F1GameStation_blockout (Autodesk Fusion 360 design; units mm, degrees)
Autodesk Fusion 360 part; units mm, degrees
sketch "Layout (front view)" plane through (0, 0, 0) normal (0, 0, 1) x (1, 0, 0)
  line L0 (-93, -40) -> (93, -40)
  line L1 (93, -40) -> (93, 40)
  line L2 (93, 40) -> (-93, 40)
  line L3 (-93, 40) -> (-93, -40)
  line L4 (-53, -33) -> (53, -33)
  line L5 (53, -33) -> (53, 34)
  line L6 (53, 34) -> (-53, 34)
  line L7 (-53, 34) -> (-53, -33)
  line L8 (-49.5, -30) -> (49.5, -30)
  line L9 (49.5, -30) -> (49.5, 26.5)
  line L10 (49.5, 26.5) -> (-49.5, 26.5)
  line L11 (-49.5, 26.5) -> (-49.5, -30)
  circle A0 centre (-73, 21) radius 3.5
  circle A1 centre (-73, 3) radius 3.5
  circle A2 centre (-82, 12) radius 3.5
  circle A3 centre (-64, 12) radius 3.5
  circle A4 centre (73, 21) radius 3.5
  circle A5 centre (73, 3) radius 3.5
  circle A6 centre (64, 12) radius 3.5
  circle A7 centre (82, 12) radius 3.5
  circle A8 centre (65.5, -18) radius 2.5
  circle A9 centre (80.5, -18) radius 2.5
  circle A10 centre (73, -29) radius 2.5
  line L12 (-78, -25.6) -> (-68, -25.6)
  line L13 (-68, -25.6) -> (-68, -24.4)
  line L14 (-68, -24.4) -> (-78, -24.4)
  line L15 (-78, -24.4) -> (-78, -25.6)
  line L16 (-78, -22.6) -> (-68, -22.6)
  line L17 (-68, -22.6) -> (-68, -21.4)
  line L18 (-68, -21.4) -> (-78, -21.4)
  line L19 (-78, -21.4) -> (-78, -22.6)
  line L20 (-78, -19.6) -> (-68, -19.6)
  line L21 (-68, -19.6) -> (-68, -18.4)
  line L22 (-68, -18.4) -> (-78, -18.4)
  line L23 (-78, -18.4) -> (-78, -19.6)
  dimension "d46" = 186
  dimension "d47" = 80
  dimension "d48" = 93
  dimension "d49" = 40
  dimension "d50" = 106
  dimension "d51" = 67
  dimension "d52" = 53
  dimension "d53" = 33
  dimension "d54" = 99
  dimension "d56" = 49.5
  dimension "d57" = 30
  dimension "d58" = 7
  dimension "d59" = 73
  dimension "d60" = 21
  dimension "d61" = 7
  dimension "d62" = 73
  dimension "d63" = 3
  dimension "d64" = 7
  dimension "d65" = 82
  dimension "d66" = 12
  dimension "d67" = 7
  dimension "d68" = 64
  dimension "d69" = 12
  dimension "d70" = 7
  dimension "d71" = 73
  dimension "d72" = 21
  dimension "d73" = 7
  dimension "d74" = 73
  dimension "d75" = 3
  dimension "d76" = 7
  dimension "d77" = 64
  dimension "d78" = 12
  dimension "d79" = 7
  dimension "d80" = 82
  dimension "d81" = 12
  dimension "d82" = 5
  dimension "d83" = 65.5
  dimension "d84" = 18
  dimension "d85" = 5
  dimension "d86" = 80.5
  dimension "d87" = 18
  dimension "d88" = 5
  dimension "d89" = 73
  dimension "d90" = 29
  dimension "d91" = 10
  dimension "d92" = 1.2
  dimension "d93" = 78
  dimension "d94" = 25.6
  dimension "d95" = 10
  dimension "d96" = 1.2
  dimension "d97" = 78
  dimension "d98" = 22.6
  dimension "d99" = 10
  dimension "d100" = 1.2
  dimension "d101" = 78
  dimension "d102" = 19.6
  constraint horizontal L0
  constraint horizontal L2
  constraint vertical L1
  constraint vertical L3
  constraint horizontal L4
  constraint horizontal L6
  constraint vertical L5
  constraint vertical L7
  constraint horizontal L8
  constraint horizontal L10
  constraint vertical L9
  constraint vertical L11
  constraint horizontal L12
  constraint horizontal L14
  constraint vertical L13
  constraint vertical L15
  constraint horizontal L16
  constraint horizontal L18
  constraint vertical L17
  constraint vertical L19
  constraint horizontal L20
  constraint horizontal L22
  constraint vertical L21
  constraint vertical L23
  measures "d46" horizontal distance of L0.start L0.end
  measures "d47" vertical distance of L0.end L1.end
  measures "d48" horizontal distance of origin L0.start
  measures "d49" vertical distance of origin L0.start
  measures "d50" horizontal distance of L4.start L4.end
  measures "d51" vertical distance of L4.end L5.end
  measures "d52" horizontal distance of origin L4.start
  measures "d53" vertical distance of origin L4.start
  measures "d54" horizontal distance of L8.start L8.end
  measures "d56" horizontal distance of origin L8.start
  measures "d57" vertical distance of origin L8.start
  measures "d58" diameter of A0
  measures "d59" horizontal distance of origin A0.centre
  measures "d60" vertical distance of origin A0.centre
  measures "d61" diameter of A1
  measures "d62" horizontal distance of origin A1.centre
  measures "d63" vertical distance of origin A1.centre
  measures "d64" diameter of A2
  measures "d65" horizontal distance of origin A2.centre
  measures "d66" vertical distance of origin A2.centre
  measures "d67" diameter of A3
  measures "d68" horizontal distance of origin A3.centre
  measures "d69" vertical distance of origin A3.centre
  measures "d70" diameter of A4
  measures "d71" horizontal distance of origin A4.centre
  measures "d72" vertical distance of origin A4.centre
  measures "d73" diameter of A5
  measures "d74" horizontal distance of origin A5.centre
  measures "d75" vertical distance of origin A5.centre
  measures "d76" diameter of A6
  measures "d77" horizontal distance of origin A6.centre
  measures "d78" vertical distance of origin A6.centre
  measures "d79" diameter of A7
  measures "d80" horizontal distance of origin A7.centre
  measures "d81" vertical distance of origin A7.centre
  measures "d82" diameter of A8
  measures "d83" horizontal distance of origin A8.centre
  measures "d84" vertical distance of origin A8.centre
  measures "d85" diameter of A9
  measures "d86" horizontal distance of origin A9.centre
  measures "d87" vertical distance of origin A9.centre
  measures "d88" diameter of A10
  measures "d89" horizontal distance of origin A10.centre
  measures "d90" vertical distance of origin A10.centre
  measures "d91" horizontal distance of L12.start L12.end
  measures "d92" vertical distance of L12.end L13.end
  measures "d93" horizontal distance of origin L12.start
  measures "d94" vertical distance of origin L12.start
  measures "d95" horizontal distance of L16.start L16.end
  measures "d96" vertical distance of L16.end L17.end
  measures "d97" horizontal distance of origin L16.start
  measures "d98" vertical distance of origin L16.start
  measures "d99" horizontal distance of L20.start L20.end
  measures "d100" vertical distance of L20.end L21.end
  measures "d101" horizontal distance of origin L20.start
  measures "d102" vertical distance of origin L20.start
ref_plane "WorkPlane1" through (0, 0, -1.6) normal (0, 0, 1) x (1, 0, 0) in component "Board envelope"
sketch "PCB" plane through (0, 0, -1.6) normal (0, 0, 1) x (1, 0, 0) in component "Board envelope"
  line L0 (-88, -35) -> (88, -35)
  line L1 (88, -35) -> (88, 35)
  line L2 (88, 35) -> (-88, 35)
  line L3 (-88, 35) -> (-88, -35)
  dimension "d105" = 176
  dimension "d106" = 70
  dimension "d107" = 88
  dimension "d108" = 35
  constraint horizontal L0
  constraint horizontal L2
  constraint vertical L1
  constraint vertical L3
  measures "d105" horizontal distance of L0.start L0.end
  measures "d106" vertical distance of L0.end L1.end
  measures "d107" horizontal distance of origin L0.start
  measures "d108" vertical distance of origin L0.start
extrude "Extrude1" add sketch "PCB" along normal blind 1.6 makes body 1 in component "Board envelope"
ref_plane "WorkPlane1" through (0, 0, 1) normal (0, 0, 1) x (1, 0, 0) in component "LCD FPC043CS4001"
sketch "LCD module" plane through (0, 0, 1) normal (0, 0, 1) x (1, 0, 0) in component "LCD FPC043CS4001"
  line L0 (-53, -33) -> (53, -33)
  line L1 (53, -33) -> (53, 34)
  line L2 (53, 34) -> (-53, 34)
  line L3 (-53, 34) -> (-53, -33)
  dimension "d113" = 106
  dimension "d114" = 67
  dimension "d115" = 53
  dimension "d116" = 33
  constraint horizontal L0
  constraint horizontal L2
  constraint vertical L1
  constraint vertical L3
  measures "d113" horizontal distance of L0.start L0.end
  measures "d114" vertical distance of L0.end L1.end
  measures "d115" horizontal distance of origin L0.start
  measures "d116" vertical distance of origin L0.start
extrude "Extrude1'" add sketch "LCD module" along normal blind 3 separate body makes body 2 in component "LCD FPC043CS4001"
ref_plane "WorkPlane2" through (0, 0, 4) normal (0, 0, 1) x (1, 0, 0) in component "LCD FPC043CS4001"
sketch "LCD visible area" plane through (0, 0, 4) normal (0, 0, 1) x (1, 0, 0) in component "LCD FPC043CS4001"
  line L0 (-49.5, -30) -> (49.5, -30)
  line L1 (49.5, -30) -> (49.5, 26.5)
  line L2 (49.5, 26.5) -> (-49.5, 26.5)
  line L3 (-49.5, 26.5) -> (-49.5, -30)
  dimension "d121" = 99
  dimension "d123" = 49.5
  dimension "d124" = 30
  constraint horizontal L0
  constraint horizontal L2
  constraint vertical L1
  constraint vertical L3
  measures "d121" horizontal distance of L0.start L0.end
  measures "d123" horizontal distance of origin L0.start
  measures "d124" vertical distance of origin L0.start
extrude "Extrude2" add sketch "LCD visible area" along normal blind 0.1 separate body makes body 3 in component "LCD FPC043CS4001"
ref_plane "WorkPlane3" through (0, 0, 0.2) normal (0, 0, 1) x (1, 0, 0) in component "LCD FPC043CS4001"
sketch "FPC wrap" plane through (0, 0, 0.2) normal (0, 0, 1) x (1, 0, 0) in component "LCD FPC043CS4001"
  line L0 (-15, 34) -> (31, 34)
  line L1 (31, 34) -> (31, 34.6)
  line L2 (31, 34.6) -> (-15, 34.6)
  line L3 (-15, 34.6) -> (-15, 34)
  dimension "d129" = 46
  dimension "d130" = 0.6
  dimension "d132" = 34
  dimension "d272" = 15
  constraint horizontal L0
  constraint horizontal L2
  constraint vertical L1
  constraint vertical L3
  measures "d129" horizontal distance of L0.start L0.end
  measures "d130" vertical distance of L0.end L1.end
  measures "d132" vertical distance of origin L0.start
  measures "d272" horizontal distance of origin L0.start
extrude "Extrude3" add sketch "FPC wrap" along normal blind 3.8 separate body makes body 4 in component "LCD FPC043CS4001"
ref_plane "WorkPlane4" through (0, 0, 0.2) normal (0, 0, 1) x (1, 0, 0) in component "LCD FPC043CS4001"
sketch "FPC tail" plane through (0, 0, 0.2) normal (0, 0, 1) x (1, 0, 0) in component "LCD FPC043CS4001"
  line L0 (-15, 2) -> (31, 2)
  line L1 (31, 2) -> (31, 34)
  line L2 (31, 34) -> (-15, 34)
  line L3 (-15, 34) -> (-15, 2)
  dimension "d137" = 46
  dimension "d138" = 32
  dimension "d140" = 2
  dimension "d273" = 15
  constraint horizontal L0
  constraint horizontal L2
  constraint vertical L1
  constraint vertical L3
  measures "d137" horizontal distance of L0.start L0.end
  measures "d138" vertical distance of L0.end L1.end
  measures "d140" vertical distance of origin L0.start
  measures "d273" horizontal distance of origin L0.start
extrude "Extrude4" add sketch "FPC tail" along normal blind 0.3 separate body makes body 5 in component "LCD FPC043CS4001"
ref_plane "WorkPlane1" through (0, 0, -10.1) normal (0, 0, 1) x (1, 0, 0) in component "Battery 606090"
sketch "Battery" plane through (0, 0, -10.1) normal (0, 0, 1) x (1, 0, 0) in component "Battery 606090"
  line L0 (-45, -27.5) -> (45, -27.5)
  line L1 (45, -27.5) -> (45, 32.5)
  line L2 (45, 32.5) -> (-45, 32.5)
  line L3 (-45, 32.5) -> (-45, -27.5)
  dimension "d145" = 90
  dimension "d146" = 60
  dimension "d147" = 45
  dimension "d349" = 27.5
  constraint horizontal L0
  constraint horizontal L2
  constraint vertical L1
  constraint vertical L3
  measures "d145" horizontal distance of L0.start L0.end
  measures "d146" vertical distance of L0.end L1.end
  measures "d147" horizontal distance of origin L0.start
  measures "d349" vertical distance of origin L0.start
extrude "Extrude1''" add sketch "Battery" along normal blind 6 separate body makes body 6 in component "Battery 606090"
ref_plane "WorkPlane1" through (0, 0, 0) normal (0, 0, 1) x (1, 0, 0) in component "Buttons"
sketch "Face buttons 1" plane through (0, 0, 0) normal (0, 0, 1) x (1, 0, 0) in component "Buttons"
  circle A0 centre (-73, 21) radius 3.5
  dimension "d153" = 7
  dimension "d154" = 73
  dimension "d155" = 21
  measures "d153" diameter of A0
  measures "d154" horizontal distance of origin A0.centre
  measures "d155" vertical distance of origin A0.centre
extrude "Extrude1'''" add sketch "Face buttons 1" along normal blind 4.5 separate body makes body 7 in component "Buttons"
sketch "Face buttons 2" plane through (0, 0, 0) normal (0, 0, 1) x (1, 0, 0) in component "Buttons"
  circle A0 centre (-73, 3) radius 3.5
  dimension "d158" = 7
  dimension "d159" = 73
  dimension "d160" = 3
  measures "d158" diameter of A0
  measures "d159" horizontal distance of origin A0.centre
  measures "d160" vertical distance of origin A0.centre
extrude "Extrude2'" add sketch "Face buttons 2" along normal blind 4.5 separate body makes body 8 in component "Buttons"
sketch "Face buttons 3" plane through (0, 0, 0) normal (0, 0, 1) x (1, 0, 0) in component "Buttons"
  circle A0 centre (-82, 12) radius 3.5
  dimension "d163" = 7
  dimension "d164" = 82
  dimension "d165" = 12
  measures "d163" diameter of A0
  measures "d164" horizontal distance of origin A0.centre
  measures "d165" vertical distance of origin A0.centre
extrude "Extrude3'" add sketch "Face buttons 3" along normal blind 4.5 separate body makes body 9 in component "Buttons"
sketch "Face buttons 4" plane through (0, 0, 0) normal (0, 0, 1) x (1, 0, 0) in component "Buttons"
  circle A0 centre (-64, 12) radius 3.5
  dimension "d168" = 7
  dimension "d169" = 64
  dimension "d170" = 12
  measures "d168" diameter of A0
  measures "d169" horizontal distance of origin A0.centre
  measures "d170" vertical distance of origin A0.centre
extrude "Extrude4'" add sketch "Face buttons 4" along normal blind 4.5 separate body makes body 10 in component "Buttons"
sketch "Face buttons 5" plane through (0, 0, 0) normal (0, 0, 1) x (1, 0, 0) in component "Buttons"
  circle A0 centre (73, 21) radius 3.5
  dimension "d173" = 7
  dimension "d174" = 73
  dimension "d175" = 21
  measures "d173" diameter of A0
  measures "d174" horizontal distance of origin A0.centre
  measures "d175" vertical distance of origin A0.centre
extrude "Extrude5" add sketch "Face buttons 5" along normal blind 4.5 separate body makes body 11 in component "Buttons"
sketch "Face buttons 6" plane through (0, 0, 0) normal (0, 0, 1) x (1, 0, 0) in component "Buttons"
  circle A0 centre (73, 3) radius 3.5
  dimension "d178" = 7
  dimension "d179" = 73
  dimension "d180" = 3
  measures "d178" diameter of A0
  measures "d179" horizontal distance of origin A0.centre
  measures "d180" vertical distance of origin A0.centre
extrude "Extrude6" add sketch "Face buttons 6" along normal blind 4.5 separate body makes body 12 in component "Buttons"
sketch "Face buttons 7" plane through (0, 0, 0) normal (0, 0, 1) x (1, 0, 0) in component "Buttons"
  circle A0 centre (64, 12) radius 3.5
  dimension "d183" = 7
  dimension "d184" = 64
  dimension "d185" = 12
  measures "d183" diameter of A0
  measures "d184" horizontal distance of origin A0.centre
  measures "d185" vertical distance of origin A0.centre
extrude "Extrude7" add sketch "Face buttons 7" along normal blind 4.5 separate body makes body 13 in component "Buttons"
sketch "Face buttons 8" plane through (0, 0, 0) normal (0, 0, 1) x (1, 0, 0) in component "Buttons"
  circle A0 centre (82, 12) radius 3.5
  dimension "d188" = 7
  dimension "d189" = 82
  dimension "d190" = 12
  measures "d188" diameter of A0
  measures "d189" horizontal distance of origin A0.centre
  measures "d190" vertical distance of origin A0.centre
extrude "Extrude8" add sketch "Face buttons 8" along normal blind 4.5 separate body makes body 14 in component "Buttons"
ref_plane "WorkPlane2" through (0, 0, 0) normal (0, 0, 1) x (1, 0, 0) in component "Buttons"
sketch "Start Select Menu 1" plane through (0, 0, 0) normal (0, 0, 1) x (1, 0, 0) in component "Buttons"
  circle A0 centre (65.5, -18) radius 2.5
  dimension "d195" = 5
  dimension "d196" = 65.5
  dimension "d197" = 18
  measures "d195" diameter of A0
  measures "d196" horizontal distance of origin A0.centre
  measures "d197" vertical distance of origin A0.centre
extrude "Extrude9" add sketch "Start Select Menu 1" along normal blind 4.5 separate body makes body 15 in component "Buttons"
sketch "Start Select Menu 2" plane through (0, 0, 0) normal (0, 0, 1) x (1, 0, 0) in component "Buttons"
  circle A0 centre (80.5, -18) radius 2.5
  dimension "d200" = 5
  dimension "d201" = 80.5
  dimension "d202" = 18
  measures "d200" diameter of A0
  measures "d201" horizontal distance of origin A0.centre
  measures "d202" vertical distance of origin A0.centre
extrude "Extrude10" add sketch "Start Select Menu 2" along normal blind 4.5 separate body makes body 16 in component "Buttons"
sketch "Start Select Menu 3" plane through (0, 0, 0) normal (0, 0, 1) x (1, 0, 0) in component "Buttons"
  circle A0 centre (73, -29) radius 2.5
  dimension "d205" = 5
  dimension "d206" = 73
  dimension "d207" = 29
  measures "d205" diameter of A0
  measures "d206" horizontal distance of origin A0.centre
  measures "d207" vertical distance of origin A0.centre
extrude "Extrude11" add sketch "Start Select Menu 3" along normal blind 4.5 separate body makes body 17 in component "Buttons"
ref_plane "WorkPlane3" through (0, 0, 0) normal (0, 0, 1) x (1, 0, 0) in component "Buttons"
ref_plane "WorkPlane4" through (0, 0, 0) normal (0, 0, 1) x (1, 0, 0) in component "Buttons"
sketch "L R switches 1" plane through (0, 0, 0) normal (0, 0, 1) x (1, 0, 0) in component "Buttons"
  line L0 (-82.25, 31.6) -> (-77.75, 31.6)
  line L1 (-77.75, 31.6) -> (-77.75, 35)
  line L2 (-77.75, 35) -> (-82.25, 35)
  line L3 (-82.25, 35) -> (-82.25, 31.6)
  dimension "d220" = 4.5
  dimension "d221" = 3.4
  dimension "d222" = 82.25
  dimension "d223" = 31.6
  constraint horizontal L0
  constraint horizontal L2
  constraint vertical L1
  constraint vertical L3
  measures "d220" horizontal distance of L0.start L0.end
  measures "d221" vertical distance of L0.end L1.end
  measures "d222" horizontal distance of origin L0.start
  measures "d223" vertical distance of origin L0.start
extrude "Extrude13" add sketch "L R switches 1" along normal blind 3.3 separate body makes body 18 in component "Buttons"
sketch "L R switches 2" plane through (0, 0, 0) normal (0, 0, 1) x (1, 0, 0) in component "Buttons"
  line L0 (77.75, 31.6) -> (82.25, 31.6)
  line L1 (82.25, 31.6) -> (82.25, 35)
  line L2 (82.25, 35) -> (77.75, 35)
  line L3 (77.75, 35) -> (77.75, 31.6)
  dimension "d226" = 4.5
  dimension "d227" = 3.4
  dimension "d228" = 77.75
  dimension "d229" = 31.6
  constraint horizontal L0
  constraint horizontal L2
  constraint vertical L1
  constraint vertical L3
  measures "d226" horizontal distance of L0.start L0.end
  measures "d227" vertical distance of L0.end L1.end
  measures "d228" horizontal distance of origin L0.start
  measures "d229" vertical distance of origin L0.start
extrude "Extrude14" add sketch "L R switches 2" along normal blind 3.3 separate body makes body 19 in component "Buttons"
ref_plane "WorkPlane1" through (0, 0, -4.86) normal (0, 0, 1) x (1, 0, 0) in component "Connectors"
sketch "USB-C" plane through (0, 0, -4.86) normal (0, 0, 1) x (1, 0, 0) in component "Connectors"
  line L0 (-4.47, -36) -> (4.47, -36)
  line L1 (4.47, -36) -> (4.47, -28.65)
  line L2 (4.47, -28.65) -> (-4.47, -28.65)
  line L3 (-4.47, -28.65) -> (-4.47, -36)
  dimension "d234" = 8.94
  dimension "d235" = 7.35
  dimension "d236" = 4.47
  dimension "d237" = 36
  constraint horizontal L0
  constraint horizontal L2
  constraint vertical L1
  constraint vertical L3
  measures "d234" horizontal distance of L0.start L0.end
  measures "d235" vertical distance of L0.end L1.end
  measures "d236" horizontal distance of origin L0.start
  measures "d237" vertical distance of origin L0.start
extrude "Extrude1''''" add sketch "USB-C" along normal blind 3.26 separate body makes body 20 in component "Connectors"
ref_plane "WorkPlane2" through (0, 0, -3.45) normal (0, 0, 1) x (1, 0, 0) in component "Connectors"
sketch "TF slot" plane through (0, 0, -3.45) normal (0, 0, 1) x (1, 0, 0) in component "Connectors"
  line L0 (45, -36) -> (59, -36)
  line L1 (59, -36) -> (59, -21)
  line L2 (59, -21) -> (45, -21)
  line L3 (45, -21) -> (45, -36)
  dimension "d242" = 14
  dimension "d243" = 15
  dimension "d244" = 45
  dimension "d245" = 36
  constraint horizontal L0
  constraint horizontal L2
  constraint vertical L1
  constraint vertical L3
  measures "d242" horizontal distance of L0.start L0.end
  measures "d243" vertical distance of L0.end L1.end
  measures "d244" horizontal distance of origin L0.start
  measures "d245" vertical distance of origin L0.start
extrude "Extrude2''" add sketch "TF slot" along normal blind 1.85 separate body makes body 21 in component "Connectors"
ref_plane "WorkPlane3" through (0, 0, -5.9) normal (0, 0, 1) x (1, 0, 0) in component "Connectors"
sketch "Battery connector" plane through (0, 0, -5.9) normal (0, 0, 1) x (1, 0, 0) in component "Connectors"
  line L0 (50, -1.5) -> (56, -1.5)
  line L1 (56, -1.5) -> (56, 6.5)
  line L2 (56, 6.5) -> (50, 6.5)
  line L3 (50, 6.5) -> (50, -1.5)
  dimension "d250" = 6
  dimension "d251" = 8
  dimension "d252" = 50
  dimension "d350" = 1.5
  constraint horizontal L0
  constraint horizontal L2
  constraint vertical L1
  constraint vertical L3
  measures "d250" horizontal distance of L0.start L0.end
  measures "d251" vertical distance of L0.end L1.end
  measures "d252" horizontal distance of origin L0.start
  measures "d350" vertical distance of origin L0.start
extrude "Extrude3''" add sketch "Battery connector" along normal blind 4.3 separate body makes body 22 in component "Connectors"
ref_plane "WorkPlane1" through (0, 0, 0) normal (0, 0, 1) x (1, 0, 0) in component "Speaker"
sketch "Speaker KLJ-01304T" plane through (0, 0, 0) normal (0, 0, 1) x (1, 0, 0) in component "Speaker"
  line L0 (-79.5, -28.5) -> (-66.5, -28.5)
  line L1 (-66.5, -28.5) -> (-66.5, -15.5)
  line L2 (-66.5, -15.5) -> (-79.5, -15.5)
  line L3 (-79.5, -15.5) -> (-79.5, -28.5)
  dimension "d258" = 13
  dimension "d259" = 13
  dimension "d260" = 79.5
  dimension "d261" = 28.5
  constraint horizontal L0
  constraint horizontal L2
  constraint vertical L1
  constraint vertical L3
  measures "d258" horizontal distance of L0.start L0.end
  measures "d259" vertical distance of L0.end L1.end
  measures "d260" horizontal distance of origin L0.start
  measures "d261" vertical distance of origin L0.start
extrude "Extrude1'''''" add sketch "Speaker KLJ-01304T" along normal blind 4 separate body makes body 23 in component "Speaker"
ref_plane "WorkPlane1" through (0, 0, -11) normal (0, 0, 1) x (1, 0, 0) in component "Case envelope"
sketch "Case envelope" plane through (0, 0, -11) normal (0, 0, 1) x (1, 0, 0) in component "Case envelope"
  line L0 (-93, -40) -> (93, -40)
  line L1 (93, -40) -> (93, 40)
  line L2 (93, 40) -> (-93, 40)
  line L3 (-93, 40) -> (-93, -40)
  dimension "d266" = 186
  dimension "d267" = 80
  dimension "d268" = 93
  dimension "d269" = 40
  constraint horizontal L0
  constraint horizontal L2
  constraint vertical L1
  constraint vertical L3
  measures "d266" horizontal distance of L0.start L0.end
  measures "d267" vertical distance of L0.end L1.end
  measures "d268" horizontal distance of origin L0.start
  measures "d269" vertical distance of origin L0.start
extrude "Extrude1''''''" add sketch "Case envelope" along normal blind 17 separate body makes body 24 in component "Case envelope"
ref_plane "WorkPlane2" through (0, 0, -1.6) normal (0, 0, 1) x (1, 0, 0) in component "Board envelope"
sketch "FPC slot" plane through (0, 0, -1.6) normal (0, 0, 1) x (1, 0, 0) in component "Board envelope"
  line L0 (-16, 0.75) -> (32, 0.75)
  line L1 (32, 0.75) -> (32, 3.25)
  line L2 (32, 3.25) -> (-16, 3.25)
  line L3 (-16, 3.25) -> (-16, 0.75)
  dimension "d284" = 48
  dimension "d285" = 2.5
  dimension "d286" = 16
  dimension "d287" = 0.75
  constraint horizontal L0
  constraint horizontal L2
  constraint vertical L1
  constraint vertical L3
  measures "d284" horizontal distance of L0.start L0.end
  measures "d285" vertical distance of L0.end L1.end
  measures "d286" horizontal distance of origin L0.start
  measures "d287" vertical distance of origin L0.start
extrude "FPC slot cut" cut sketch "FPC slot" along normal blind 1.6 bodies 1 in component "Board envelope"
ref_plane "WorkPlane5" through (0, 0, -1.9) normal (0, 0, 1) x (1, 0, 0) in component "LCD FPC043CS4001"
sketch "FPC through slot" plane through (0, 0, -1.9) normal (0, 0, 1) x (1, 0, 0) in component "LCD FPC043CS4001"
  line L0 (-15, 1.85) -> (31, 1.85)
  line L1 (31, 1.85) -> (31, 2.15)
  line L2 (31, 2.15) -> (-15, 2.15)
  line L3 (-15, 2.15) -> (-15, 1.85)
  dimension "d292" = 46
  dimension "d293" = 0.3
  dimension "d294" = 15
  dimension "d295" = 1.85
  constraint horizontal L0
  constraint horizontal L2
  constraint vertical L1
  constraint vertical L3
  measures "d292" horizontal distance of L0.start L0.end
  measures "d293" vertical distance of L0.end L1.end
  measures "d294" horizontal distance of origin L0.start
  measures "d295" vertical distance of origin L0.start
extrude "Extrude5'" add sketch "FPC through slot" along normal blind 2.1 separate body makes body 25 in component "LCD FPC043CS4001"
ref_plane "WorkPlane6" through (0, 0, -1.9) normal (0, 0, 1) x (1, 0, 0) in component "LCD FPC043CS4001"
sketch "FPC on PCB back" plane through (0, 0, -1.9) normal (0, 0, 1) x (1, 0, 0) in component "LCD FPC043CS4001"
  line L0 (10, -6) -> (31, -6)
  line L1 (31, -6) -> (31, 2)
  line L2 (31, 2) -> (10, 2)
  line L3 (10, 2) -> (10, -6)
  dimension "d300" = 21
  dimension "d301" = 8
  dimension "d303" = 6
  dimension "d360" = 10
  constraint horizontal L0
  constraint horizontal L2
  constraint vertical L1
  constraint vertical L3
  measures "d300" horizontal distance of L0.start L0.end
  measures "d301" vertical distance of L0.end L1.end
  measures "d303" vertical distance of origin L0.start
  measures "d360" horizontal distance of origin L0.start
extrude "Extrude6'" add sketch "FPC on PCB back" along normal blind 0.3 separate body makes body 26 in component "LCD FPC043CS4001"
ref_plane "WorkPlane1" through (0, 0, -3.6) normal (0, 0, 1) x (1, 0, 0) in component "J2 LCD connector"
sketch "J2 AFC01-S40FCA-00" plane through (0, 0, -3.6) normal (0, 0, 1) x (1, 0, 0) in component "J2 LCD connector"
  line L0 (7.8, -10.6) -> (33.2, -10.6)
  line L1 (33.2, -10.6) -> (33.2, -6)
  line L2 (33.2, -6) -> (7.8, -6)
  line L3 (7.8, -6) -> (7.8, -10.6)
  dimension "d308" = 25.4
  dimension "d309" = 4.6
  dimension "d311" = 10.6
  dimension "d361" = 7.8
  constraint horizontal L0
  constraint horizontal L2
  constraint vertical L1
  constraint vertical L3
  measures "d308" horizontal distance of L0.start L0.end
  measures "d309" vertical distance of L0.end L1.end
  measures "d311" vertical distance of origin L0.start
  measures "d361" horizontal distance of origin L0.start
extrude "Extrude1'''''''" add sketch "J2 AFC01-S40FCA-00" along normal blind 2 separate body makes body 27 in component "J2 LCD connector"
ref_plane "WorkPlane5" through (0, 0, -4) normal (0, 0, 1) x (1, 0, 0) in component "Buttons"
sketch "L trigger 1" plane through (0, 0, -4) normal (0, 0, 1) x (1, 0, 0) in component "Buttons"
  line L0 (-94, 36) -> (-62, 36)
  line L1 (-62, 36) -> (-62, 41)
  line L2 (-62, 41) -> (-94, 41)
  line L3 (-94, 41) -> (-94, 36)
  dimension "d322" = 32
  dimension "d323" = 5
  dimension "d324" = 94
  dimension "d325" = 36
  constraint horizontal L0
  constraint horizontal L2
  constraint vertical L1
  constraint vertical L3
  measures "d322" horizontal distance of L0.start L0.end
  measures "d323" vertical distance of L0.end L1.end
  measures "d324" horizontal distance of origin L0.start
  measures "d325" vertical distance of origin L0.start
extrude "Extrude15" add sketch "L trigger 1" along normal blind 9 separate body makes body 28 in component "Buttons"
sketch "L trigger 2" plane through (0, 0, -4) normal (0, 0, 1) x (1, 0, 0) in component "Buttons"
  line L0 (-94, 29) -> (-89, 29)
  line L1 (-89, 29) -> (-89, 41)
  line L2 (-89, 41) -> (-94, 41)
  line L3 (-94, 41) -> (-94, 29)
  dimension "d328" = 5
  dimension "d329" = 12
  dimension "d330" = 94
  dimension "d331" = 29
  constraint horizontal L0
  constraint horizontal L2
  constraint vertical L1
  constraint vertical L3
  measures "d328" horizontal distance of L0.start L0.end
  measures "d329" vertical distance of L0.end L1.end
  measures "d330" horizontal distance of origin L0.start
  measures "d331" vertical distance of origin L0.start
extrude "Extrude16" add sketch "L trigger 2" along normal blind 9 separate body makes body 29 in component "Buttons"
combine "Combine1" operation add target body 28 tool bodies 29 in component "Buttons"
ref_plane "WorkPlane6" through (0, 0, -4) normal (0, 0, 1) x (1, 0, 0) in component "Buttons"
sketch "R trigger 1" plane through (0, 0, -4) normal (0, 0, 1) x (1, 0, 0) in component "Buttons"
  line L0 (62, 36) -> (94, 36)
  line L1 (94, 36) -> (94, 41)
  line L2 (94, 41) -> (62, 41)
  line L3 (62, 41) -> (62, 36)
  dimension "d336" = 32
  dimension "d337" = 5
  dimension "d338" = 62
  dimension "d339" = 36
  constraint horizontal L0
  constraint horizontal L2
  constraint vertical L1
  constraint vertical L3
  measures "d336" horizontal distance of L0.start L0.end
  measures "d337" vertical distance of L0.end L1.end
  measures "d338" horizontal distance of origin L0.start
  measures "d339" vertical distance of origin L0.start
extrude "Extrude17" add sketch "R trigger 1" along normal blind 9 separate body makes body 30 in component "Buttons"
sketch "R trigger 2" plane through (0, 0, -4) normal (0, 0, 1) x (1, 0, 0) in component "Buttons"
  line L0 (89, 29) -> (94, 29)
  line L1 (94, 29) -> (94, 41)
  line L2 (94, 41) -> (89, 41)
  line L3 (89, 41) -> (89, 29)
  dimension "d342" = 5
  dimension "d343" = 12
  dimension "d344" = 89
  dimension "d345" = 29
  constraint horizontal L0
  constraint horizontal L2
  constraint vertical L1
  constraint vertical L3
  measures "d342" horizontal distance of L0.start L0.end
  measures "d343" vertical distance of L0.end L1.end
  measures "d344" horizontal distance of origin L0.start
  measures "d345" vertical distance of origin L0.start
extrude "Extrude18" add sketch "R trigger 2" along normal blind 9 separate body makes body 31 in component "Buttons"
combine "Combine2" operation add target body 30 tool bodies 31 in component "Buttons"
ref_plane "WorkPlane7" through (0, 0, 0) normal (0, 0, 1) x (1, 0, 0) in component "Buttons"
sketch "Power switch" plane through (0, 0, 0) normal (0, 0, 1) x (1, 0, 0) in component "Buttons"
  line L0 (84.6, -14.25) -> (88, -14.25)
  line L1 (88, -14.25) -> (88, -9.75)
  line L2 (88, -9.75) -> (84.6, -9.75)
  line L3 (84.6, -9.75) -> (84.6, -14.25)
  dimension "d353" = 3.4
  dimension "d354" = 4.5
  dimension "d355" = 84.6
  dimension "d356" = 14.25
  constraint horizontal L0
  constraint horizontal L2
  constraint vertical L1
  constraint vertical L3
  measures "d353" horizontal distance of L0.start L0.end
  measures "d354" vertical distance of L0.end L1.end
  measures "d355" horizontal distance of origin L0.start
  measures "d356" vertical distance of origin L0.start
extrude "Extrude19" add sketch "Power switch" along normal blind 3.3 separate body makes body 32 in component "Buttons"
component "Board envelope" placed x (1, 0, 0) y (0, 1, 0) z (0, 0, 1) at (0, 0, 0)
component "LCD FPC043CS4001" placed x (1, 0, 0) y (0, 1, 0) z (0, 0, 1) at (0, 0, 0)
component "Battery 606090" placed x (1, 0, 0) y (0, 1, 0) z (0, 0, 1) at (0, 0, 0)
component "Buttons" placed x (1, 0, 0) y (0, 1, 0) z (0, 0, 1) at (0, 0, 0)
component "Connectors" placed x (1, 0, 0) y (0, 1, 0) z (0, 0, 1) at (0, 0, 0)
component "Speaker" placed x (1, 0, 0) y (0, 1, 0) z (0, 0, 1) at (0, 0, 0)
component "Case envelope" placed x (1, 0, 0) y (0, 1, 0) z (0, 0, 1) at (0, 0, 0)
component "J2 LCD connector" placed x (1, 0, 0) y (0, 1, 0) z (0, 0, 1) at (0, 0, 0)
equation "case_w = 186 mm" comment "Case width (PSP-style landscape)"
equation "case_h = 80 mm" comment "Case height"
equation "case_front_z = 6 mm" comment "Case front face Z"
equation "case_back_z = -11 mm" comment "Case back face Z"
equation "pcb_w = 176 mm" comment "PCB width"
equation "pcb_h = 70 mm" comment "PCB height (clears the triggers)"
equation "pcb_t = 1.6 mm" comment "PCB thickness"
equation "panel_w = 106 mm" comment "LCD module outline width (measured)"
equation "panel_h = 67 mm" comment "LCD module outline height (measured)"
equation "panel_t = 3 mm" comment "LCD module thickness"
equation "panel_gap = 1 mm" comment "Gap PCB front to LCD back"
equation "aa_side = 3.5 mm" comment "LCD border left/right (measured)"
equation "aa_fpc = 7.5 mm" comment "LCD border on the FPC edge (measured)"
equation "aa_opp = 3 mm" comment "LCD border opposite the FPC (measured)"
equation "lcd_cx = 0 mm" comment "LCD centre X"
equation "lcd_top_margin = 6 mm" comment "Case top edge to LCD module top"
equation "fpc_w = 46 mm" comment "FPC width at the panel edge (measured)"
equation "fpc_x = 8 mm" comment "FPC centre X offset from LCD centre (right edge 22 mm from panel right, measured)"
equation "fpc_len = ( case_h / 2 - lcd_top_margin ) - slot_y + 3 mm" comment "FPC length from panel edge"
equation "fpc_t = 0.3 mm" comment "FPC thickness"
equation "bat_w = 90 mm" comment "Battery length (along X)"
equation "bat_h = 60 mm" comment "Battery width (along Y)"
equation "bat_t = 6 mm" comment "Battery thickness"
equation "bat_cy = 2.5 mm" comment "Battery centre Y (clears USB-C on the back)"
equation "bat_gap = 2.5 mm" comment "Gap PCB back to battery (clears J2 and the FPC)"
equation "pad_y = 12 mm" comment "D-pad / ABXY centre Y"
equation "dpad_x = -73 mm" comment "D-pad centre X"
equation "abxy_x = 73 mm" comment "ABXY centre X"
equation "btn_pitch = 9 mm" comment "D-pad / ABXY button offset from centre"
equation "face_d = 7 mm" comment "Face button cap diameter"
equation "btn_h = 4.5 mm" comment "Button cap top above PCB"
equation "ss_y = -18 mm" comment "Start/Select Y (below ABXY)"
equation "ss_x = 73 mm" comment "Start/Select centre X"
equation "ss_dx = 7.5 mm" comment "Start/Select X offset"
equation "menu_x = 73 mm" comment "Menu X"
equation "menu_y = -29 mm" comment "Menu Y"
equation "small_d = 5 mm" comment "Small button cap diameter"
equation "lr_x = 80 mm" comment "L/R shoulder X offset"
equation "pwr_x = -30 mm" comment "Power button X (top edge, side-push)"
equation "usb_x = 0 mm" comment "USB-C centre X (bottom edge, PCB back)"
equation "tf_x = -38 mm" comment "TF slot centre X (bottom edge, PCB back; under the SoC SD pins, clear of the M2 hole)"
equation "spk_x = -73 mm" comment "Speaker centre X (below D-pad)"
equation "spk_y = -22 mm" comment "Speaker centre Y"
equation "spk_s = 13 mm" comment "Speaker size"
equation "spk_t = 4 mm" comment "Speaker height"
equation "d46 = case_w"
equation "d47 = case_h"
equation "d48 = abs(( 0 mm ) - ( case_w ) / 2)"
equation "d49 = abs(( 0 mm ) - ( case_h ) / 2)"
equation "d50 = panel_w"
equation "d51 = panel_h"
equation "d52 = abs(( lcd_cx ) - ( panel_w ) / 2)"
equation "d53 = abs(( ( case_h / 2 - lcd_top_margin - panel_h / 2 ) ) - ( panel_h ) / 2)"
equation "d54 = ( panel_w - 2 * aa_side )"
equation "d55 = ( panel_h - aa_fpc - aa_opp )"
equation "d56 = abs(( lcd_cx ) - ( ( panel_w - 2 * aa_side ) ) / 2)"
equation "d57 = abs(( ( ( case_h / 2 - lcd_top_margin - panel_h / 2 ) + ( aa_opp - aa_fpc ) / 2 ) ) - ( ( panel_h - aa_fpc - aa_opp ) ) / 2)"
equation "d58 = face_d"
equation "d59 = abs(dpad_x)"
equation "d60 = abs(pad_y + btn_pitch)"
equation "d61 = face_d"
equation "d62 = abs(dpad_x)"
equation "d63 = abs(pad_y - btn_pitch)"
equation "d64 = face_d"
equation "d65 = abs(dpad_x - btn_pitch)"
equation "d66 = abs(pad_y)"
equation "d67 = face_d"
equation "d68 = abs(dpad_x + btn_pitch)"
equation "d69 = abs(pad_y)"
equation "d70 = face_d"
equation "d71 = abs(abxy_x)"
equation "d72 = abs(pad_y + btn_pitch)"
equation "d73 = face_d"
equation "d74 = abs(abxy_x)"
equation "d75 = abs(pad_y - btn_pitch)"
equation "d76 = face_d"
equation "d77 = abs(abxy_x - btn_pitch)"
equation "d78 = abs(pad_y)"
equation "d79 = face_d"
equation "d80 = abs(abxy_x + btn_pitch)"
equation "d81 = abs(pad_y)"
equation "d82 = small_d"
equation "d83 = abs(ss_x - ss_dx)"
equation "d84 = abs(ss_y)"
equation "d85 = small_d"
equation "d86 = abs(ss_x + ss_dx)"
equation "d87 = abs(ss_y)"
equation "d88 = small_d"
equation "d89 = abs(menu_x)"
equation "d90 = abs(menu_y)"
equation "d91 = spk_s - 3 mm"
equation "d93 = abs(( spk_x ) - ( spk_s - 3 mm ) / 2)"
equation "d94 = abs(( spk_y + -1 * 3 mm ) - ( 1.2 mm ) / 2)"
equation "d95 = spk_s - 3 mm"
equation "d97 = abs(( spk_x ) - ( spk_s - 3 mm ) / 2)"
equation "d98 = abs(( spk_y + 0 * 3 mm ) - ( 1.2 mm ) / 2)"
equation "d99 = spk_s - 3 mm"
equation "d101 = abs(( spk_x ) - ( spk_s - 3 mm ) / 2)"
equation "d102 = abs(( spk_y + 1 * 3 mm ) - ( 1.2 mm ) / 2)"
equation "d103 = -pcb_t"
equation "d105 = pcb_w"
equation "d106 = pcb_h"
equation "d107 = abs(( 0 mm ) - ( pcb_w ) / 2)"
equation "d108 = abs(( 0 mm ) - ( pcb_h ) / 2)"
equation "d109 = pcb_t"
equation "d111 = panel_gap"
equation "d113 = panel_w"
equation "d114 = panel_h"
equation "d115 = abs(( lcd_cx ) - ( panel_w ) / 2)"
equation "d116 = abs(( ( case_h / 2 - lcd_top_margin - panel_h / 2 ) ) - ( panel_h ) / 2)"
equation "d117 = panel_t"
equation "d119 = panel_gap + panel_t"
equation "d121 = ( panel_w - 2 * aa_side )"
equation "d122 = ( panel_h - aa_fpc - aa_opp )"
equation "d123 = abs(( lcd_cx ) - ( ( panel_w - 2 * aa_side ) ) / 2)"
equation "d124 = abs(( ( ( case_h / 2 - lcd_top_margin - panel_h / 2 ) + ( aa_opp - aa_fpc ) / 2 ) ) - ( ( panel_h - aa_fpc - aa_opp ) ) / 2)"
equation "d129 = fpc_w"
equation "d130 = 2 * fpc_t"
equation "d132 = abs(( ( case_h / 2 - lcd_top_margin ) + fpc_t ) - ( 2 * fpc_t ) / 2)"
equation "d133 = panel_gap + panel_t - 0.2 mm"
equation "d137 = fpc_w"
equation "d138 = fpc_len - 3 mm"
equation "d140 = abs(( ( case_h / 2 - lcd_top_margin ) - ( fpc_len - 3 mm ) / 2 ) - ( fpc_len - 3 mm ) / 2)"
equation "d141 = fpc_t"
equation "d143 = -pcb_t - bat_gap - bat_t"
equation "d145 = bat_w"
equation "d146 = bat_h"
equation "d147 = abs(( 0 mm ) - ( bat_w ) / 2)"
equation "d149 = bat_t"
equation "d153 = face_d"
equation "d154 = abs(dpad_x)"
equation "d155 = abs(pad_y + btn_pitch)"
equation "d156 = btn_h"
equation "d158 = face_d"
equation "d159 = abs(dpad_x)"
equation "d160 = abs(pad_y - btn_pitch)"
equation "d161 = btn_h"
equation "d163 = face_d"
equation "d164 = abs(dpad_x - btn_pitch)"
equation "d165 = abs(pad_y)"
equation "d166 = btn_h"
equation "d168 = face_d"
equation "d169 = abs(dpad_x + btn_pitch)"
equation "d170 = abs(pad_y)"
equation "d171 = btn_h"
equation "d173 = face_d"
equation "d174 = abs(abxy_x)"
equation "d175 = abs(pad_y + btn_pitch)"
equation "d176 = btn_h"
equation "d178 = face_d"
equation "d179 = abs(abxy_x)"
equation "d180 = abs(pad_y - btn_pitch)"
equation "d181 = btn_h"
equation "d183 = face_d"
equation "d184 = abs(abxy_x - btn_pitch)"
equation "d185 = abs(pad_y)"
equation "d186 = btn_h"
equation "d188 = face_d"
equation "d189 = abs(abxy_x + btn_pitch)"
equation "d190 = abs(pad_y)"
equation "d191 = btn_h"
equation "d195 = small_d"
equation "d196 = abs(ss_x - ss_dx)"
equation "d197 = abs(ss_y)"
equation "d198 = btn_h"
equation "d200 = small_d"
equation "d201 = abs(ss_x + ss_dx)"
equation "d202 = abs(ss_y)"
equation "d203 = btn_h"
equation "d205 = small_d"
equation "d206 = abs(menu_x)"
equation "d207 = abs(menu_y)"
equation "d208 = btn_h"
equation "d222 = abs(( -lr_x ) - ( 4.5 mm ) / 2)"
equation "d223 = abs(( pcb_h / 2 - 1.7 mm ) - ( 3.4 mm ) / 2)"
equation "d228 = abs(( lr_x ) - ( 4.5 mm ) / 2)"
equation "d229 = abs(( pcb_h / 2 - 1.7 mm ) - ( 3.4 mm ) / 2)"
equation "d232 = -pcb_t - 3.26 mm"
equation "d236 = abs(( usb_x ) - ( 8.94 mm ) / 2)"
equation "d237 = abs(( -pcb_h / 2 + 7.35 mm / 2 - 1 mm ) - ( 7.35 mm ) / 2)"
equation "d240 = -pcb_t - 1.85 mm"
equation "d244 = abs(( tf_x ) - ( 14 mm ) / 2)"
equation "d245 = abs(( -pcb_h / 2 + 15 mm / 2 - 1 mm ) - ( 15 mm ) / 2)"
equation "d248 = -pcb_t - 4.3 mm"
equation "d252 = abs(( bat_w / 2 + 8 mm ) - ( 6 mm ) / 2)"
equation "d258 = spk_s"
equation "d259 = spk_s"
equation "d260 = abs(( spk_x ) - ( spk_s ) / 2)"
equation "d261 = abs(( spk_y ) - ( spk_s ) / 2)"
equation "d262 = spk_t"
equation "d264 = case_back_z"
equation "d266 = case_w"
equation "d267 = case_h"
equation "d268 = abs(( 0 mm ) - ( case_w ) / 2)"
equation "d269 = abs(( 0 mm ) - ( case_h ) / 2)"
equation "d270 = case_front_z - case_back_z"
equation "d272 = abs(( lcd_cx + fpc_x ) - ( fpc_w ) / 2)"
equation "d273 = abs(( lcd_cx + fpc_x ) - ( fpc_w ) / 2)"
equation "slot_y = 2 mm" comment "PCB FPC slot centre Y (behind the screen)"
equation "slot_h = 2.5 mm" comment "PCB FPC slot height"
equation "slot_clear = 1 mm" comment "Slot clearance each side of the FPC"
equation "fpc_back_len = 8 mm" comment "FPC length on the PCB back, slot to connector"
equation "fpc_conn_w = 21 mm" comment "FPC width at the connector end"
equation "j2_w = 25.4 mm" comment "J2 AFC01-S40FCA-00 body width"
equation "j2_d = 4.6 mm" comment "J2 body depth"
equation "j2_t = 2 mm" comment "J2 body height"
equation "d282 = -pcb_t"
equation "d284 = fpc_w + 2 * slot_clear"
equation "d285 = slot_h"
equation "d286 = abs(( lcd_cx + fpc_x ) - ( fpc_w + 2 * slot_clear ) / 2)"
equation "d287 = abs(( slot_y ) - ( slot_h ) / 2)"
equation "d288 = pcb_t"
equation "d290 = -pcb_t - fpc_t"
equation "d292 = fpc_w"
equation "d293 = fpc_t"
equation "d294 = abs(( lcd_cx + fpc_x ) - ( fpc_w ) / 2)"
equation "d295 = abs(( slot_y ) - ( fpc_t ) / 2)"
equation "d296 = pcb_t + fpc_t + 0.2 mm"
equation "d298 = -pcb_t - fpc_t"
equation "d300 = fpc_conn_w"
equation "d301 = fpc_back_len"
equation "d303 = abs(( slot_y - fpc_back_len / 2 ) - ( fpc_back_len ) / 2)"
equation "d304 = fpc_t"
equation "d306 = -pcb_t - j2_t"
equation "d308 = j2_w"
equation "d309 = j2_d"
equation "d311 = abs(( slot_y - fpc_back_len - j2_d / 2 ) - ( j2_d ) / 2)"
equation "d312 = j2_t"
equation "trig_len = 32 mm" comment "Trigger length along the top edge"
equation "trig_wrap = 12 mm" comment "Trigger wrap down the side edge"
equation "trig_depth = 5 mm" comment "Trigger depth into the case"
equation "trig_out = 1 mm" comment "Trigger stand-out beyond the case outline"
equation "trig_z0 = -4 mm" comment "Trigger bottom Z"
equation "trig_t = 9 mm" comment "Trigger height"
equation "d320 = trig_z0"
equation "d322 = trig_len"
equation "d323 = trig_depth"
equation "d324 = abs(( -( case_w / 2 - trig_len / 2 + trig_out ) ) - ( trig_len ) / 2)"
equation "d325 = abs(( case_h / 2 - trig_depth / 2 + trig_out ) - ( trig_depth ) / 2)"
equation "d326 = trig_t"
equation "d328 = trig_depth"
equation "d329 = trig_wrap"
equation "d330 = abs(( -( case_w / 2 - trig_depth / 2 + trig_out ) ) - ( trig_depth ) / 2)"
equation "d331 = abs(( case_h / 2 - trig_wrap / 2 + trig_out ) - ( trig_wrap ) / 2)"
equation "d332 = trig_t"
equation "d334 = trig_z0"
equation "d336 = trig_len"
equation "d337 = trig_depth"
equation "d338 = abs(( ( case_w / 2 - trig_len / 2 + trig_out ) ) - ( trig_len ) / 2)"
equation "d339 = abs(( case_h / 2 - trig_depth / 2 + trig_out ) - ( trig_depth ) / 2)"
equation "d340 = trig_t"
equation "d342 = trig_depth"
equation "d343 = trig_wrap"
equation "d344 = abs(( ( case_w / 2 - trig_depth / 2 + trig_out ) ) - ( trig_depth ) / 2)"
equation "d345 = abs(( case_h / 2 - trig_wrap / 2 + trig_out ) - ( trig_wrap ) / 2)"
equation "d346 = trig_t"
equation "pwr_y = -12 mm" comment "Power button Y (right side edge, side-push)"
equation "d349 = abs(( bat_cy ) - ( bat_h ) / 2)"
equation "d350 = abs(( bat_cy ) - ( 8 mm ) / 2)"
equation "d355 = abs(( pcb_w / 2 - 1.7 mm ) - ( 3.4 mm ) / 2)"
equation "d356 = abs(( pwr_y ) - ( 4.5 mm ) / 2)"
equation "fpc_conn_x = 20.5 mm" comment "FPC connector-end centre X from LCD centre (tail runs +10..+31, user)"
equation "d360 = abs(( lcd_cx + fpc_conn_x ) - ( fpc_conn_w ) / 2)"
equation "d361 = abs(( lcd_cx + fpc_conn_x ) - ( j2_w ) / 2)"
named bodies: "PCB", "LCD module", "LCD visible area", "FPC wrap", "FPC tail", "Battery", "Face buttons 1", "Face buttons 2", "Face buttons 3", "Face buttons 4", "Face buttons 5", "Face buttons 6", "Face buttons 7", "Face buttons 8", "Start Select Menu 1", "Start Select Menu 2", "Start Select Menu 3", "L R switches 1", "L R switches 2", "USB-C", "TF slot", "Battery connector", "Speaker KLJ-01304T", "Case envelope", "FPC through slot", "FPC on PCB back", "J2 AFC01-S40FCA-00", "L trigger", "L trigger 2", "R trigger", "R trigger 2", "Power switch"
